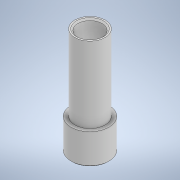
# Autodesk Inventor part: sup_diode3mm
Saved by Autodesk Inventor 2021.5 (Build 255421000, 421)
## iProperties
Created: 2026-10-01
Part Number: sup_diode3mm
Material: Générique
Document SubType Name: Modeling
Designer: Christophe
Density: 1 g/cm^3
Appearance: Par défaut
Author: Christophe
Autodesk Inventor part; units mm, degrees
ref_plane "YZ Plane" through (0, 0, 0) normal (1, 0, 0) x (0, 1, 0)
ref_plane "XZ Plane" through (0, 0, 0) normal (0, 1, 0) x (-1, 0, 0)
ref_plane "XY Plane" through (0, 0, 0) normal (0, 0, 1) x (1, 0, 0)
sketch "Esquisse1" plane through (0, 0, 0) normal (0, 1, 0) x (-1, 0, 0)
  circle A0 centre (0, 0) radius 6.25
  dimension "d0" = 12.5
  constraints: 1 centre point, 1 coincident
  measures "d0" diameter of A0
extrude "Extrusion1" add sketch "Esquisse1" along normal blind 10
chamfer "Chanfrein2" distance 0.3 angle 45 1 edges at (6.25, 0, 0)
sketch "Esquisse5" plane through (0, 10, 0) normal (0, 1, 0) x (1, 0, 0)
  circle A0 centre (0, 0) radius 5
  dimension "d22" = 10
  constraints: 1 centre point, 1 coincident
  measures "d22" diameter of A0
extrude "Extrusion4" add sketch "Esquisse5" along normal blind 25
sketch "Esquisse6" plane through (0, 35, 0) normal (0, 1, 0) x (1, 0, 0)
  point P0 (0, 0)
hole "Perçage2" at (0, 35, 0) direction (0, -1, 0) diameter 3.2 end through all counterbore diameter 8 counterbore depth 32
chamfer "Chanfrein3" distance 0.5 angle 45 1 edges at (0, 0, -1.6)
chamfer "Chanfrein4" distance 0.5 angle 45 1 edges at (0, 35, -4)
